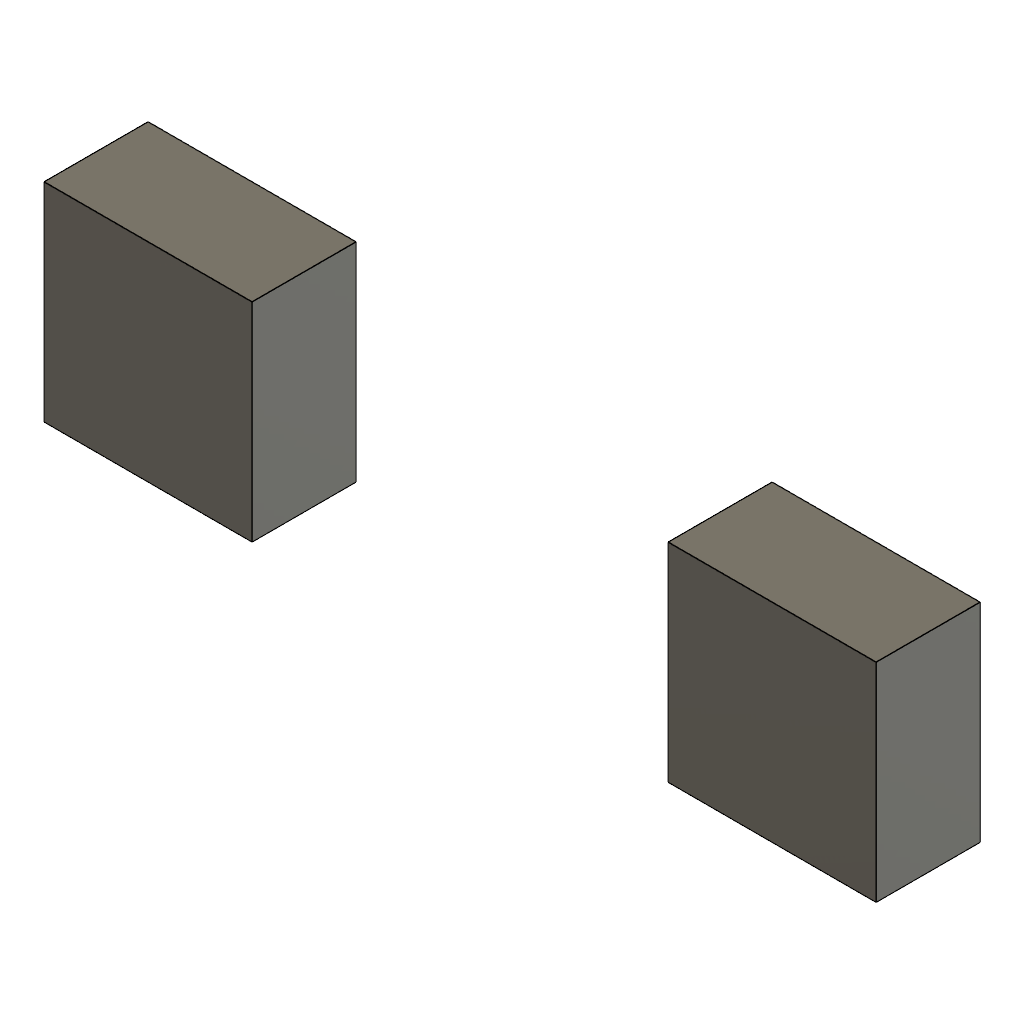
mirror_body (Autodesk Fusion 360 design; units mm, degrees)
part number: 2026-11-13-14-44-21-107
Autodesk Fusion 360 part; units mm, degrees
sketch "Sketch1" plane through (0, 0, 0) normal (0, 0, 1) x (1, 0, 0)
  line L0 (10, 5) -> (20, 5)
  line L1 (20, 5) -> (20, 15)
  line L2 (20, 15) -> (10, 15)
  line L3 (10, 15) -> (10, 5)
extrude "Extrude1" add sketch "Sketch1" along normal blind 5 makes body 1
mirror "Mirror1" about plane through (0, 0, 0) normal (1, 0, 0) of bodies 1 makes body 2
